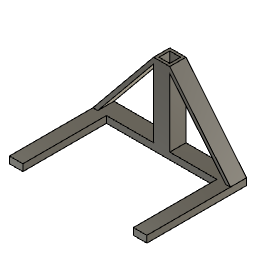
Endurancetestbase v2 (Autodesk Fusion 360 design; units mm, degrees)
Autodesk Fusion 360 part; units mm, degrees
sketch "Sketch1" plane through (0, 0, 0) normal (0, 0, 1) x (1, 0, 0)
  line L0 (41, -31) -> (41, 31)
  line L1 (41, 31) -> (-41, 31)
  line L2 (-41, 31) -> (-41, -31)
  line L3 (51, -31) -> (51, 43)
  line L4 (51, 43) -> (-51, 43)
  line L5 (-51, 43) -> (-51, -31)
  line L6 (-36.7674, 31) -> (-51, 43) construction
  line L7 (-41, -31) -> (-51, -31)
  line L8 (41, -31) -> (51, -31)
  line L9 (36.7674, 31) -> (51, 43) construction
  constraint parallel L0 L2
  constraint parallel L3 L5
  constraint coincident L6 origin
  constraint perpendicular L5 L7
  constraint perpendicular L3 L8
  constraint coincident L1 L9.start
  constraint coincident L1 L6.start
extrude "Extrude1" add sketch "Sketch1" along normal blind 5
box "BoxPrimitive1" add length 12 width 12 height 55 placed x (0, -1, 0) y (1, 0, 0) z (0, 0, 1) at (-6, 43, 5)
box "BoxPrimitive2" cut length 8 width 8 height -53 placed x (0, 1, 0) y (-1, 0, 0) z (0, 0, 1) at (4, 33, 60)
sketch "Sketch4" plane through (0, 43, 0) normal (0, 1, 0) x (-1, 0, 0)
  line L0 (-51, 0) -> (51, 0)
  line L1 (51, 0) -> (51, 5)
  line L2 (51, 5) -> (6, 5)
  line L3 (6, 5) -> (6, 60)
  line L4 (6, 60) -> (-6, 60)
  line L5 (-6, 60) -> (-6, 5)
  line L6 (-6, 5) -> (-51, 5)
  line L7 (-51, 5) -> (-51, 0)
  line L8 (-6, 60) -> (-51, 5)
  line L9 (-47.4123, 5) -> (-6, 55.6151)
  line L10 (-47.4123, 5) -> (-51, 5)
  line L11 (-6, 55.6151) -> (-6, 60)
  line L12 (0, 0) -> (0, 5)
  line L13 (47.4123, 5) -> (6, 55.6151)
  line L14 (6, 55.6151) -> (6, 60)
  line L15 (6, 60) -> (51, 5)
  line L16 (47.4123, 5) -> (51, 5)
  constraint coincident L4.end L5.start
  constraint coincident L6.end L7.start
  constraint coincident L6 L9.start
  constraint coincident L5 L9.end
  constraint parallel L8 L9
  constraint perpendicular L7 L10
  constraint perpendicular L4 L11
  constraint coincident L12.start origin
  constraint perpendicular L0 L12
  constraint symmetric L4.end L12 L3.end
  constraint symmetric L6.end L12 L1.end
  constraint symmetric L9.start L12 L13.start
  constraint symmetric L9.end L12 L13.end
extrude "Extrude2" add sketch "Sketch4" against normal blind 12 contours L5 L6 L8 L9 L10 L11 | L2 L3 L13 L14 L15 L16
hole "Hole1" at (0.1124, 43, 53.682) direction (0, -1, 0) diameter 2.8 depth 5 tip angle 118
